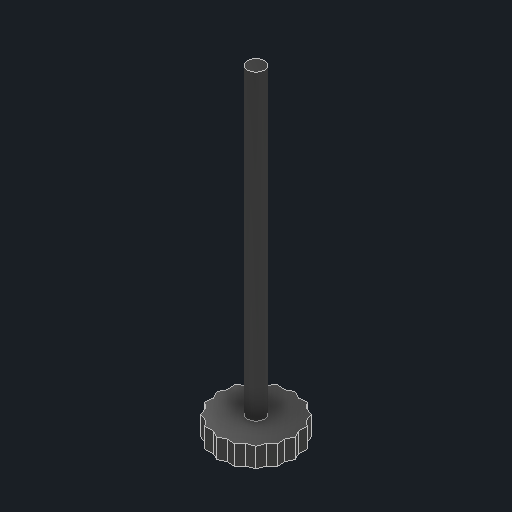
# Autodesk Inventor part: tripod_tension_rod
Saved by Autodesk Inventor 2027.1 (Build 311270010, 270A)
## iProperties
Created: 2026-11-04
Part Number: tripod_tension_rod
Material: Generic
Description: Centre tension rod + tray knob
Document SubType Name: Modeling
Designer: Claude (from photos)
Density: 1 g/cm^3
Appearance: Glossy - Black
Author: alexg
Autodesk Inventor part; units mm, degrees
ref_plane "YZ Plane" through (0, 0, 0) normal (1, 0, 0) x (0, 1, 0)
ref_plane "Work Plane1" through (0, -38, 0) normal (0, 1, 0) x (-1, 0, 0)
sketch "Centre rod M12 sketch" plane through (0, -38, 0) normal (0, 1, 0) x (-1, 0, 0)
  circle A0 centre (0, 0) radius 6
  constraints: 1 centre point
extrude "Centre rod M12" add sketch "Centre rod M12 sketch" against normal blind 236
ref_plane "Work Plane2" through (0, -254, 0) normal (0, 1, 0) x (-1, 0, 0)
sketch "Tension knob sketch" plane through (0, -254, 0) normal (0, 1, 0) x (-1, 0, 0)
  line L0 (-28, 0) -> (-25.5004, 5.0723)
  line L1 (-25.5004, 5.0723) -> (-25.8686, 10.7151)
  line L2 (-25.8686, 10.7151) -> (-21.6182, 14.4448)
  line L3 (-21.6182, 14.4448) -> (-19.799, 19.799)
  line L4 (-19.799, 19.799) -> (-14.4448, 21.6182)
  line L5 (-14.4448, 21.6182) -> (-10.7151, 25.8686)
  line L6 (-10.7151, 25.8686) -> (-5.0723, 25.5004)
  line L7 (-5.0723, 25.5004) -> (0, 28)
  line L8 (0, 28) -> (5.0723, 25.5004)
  line L9 (5.0723, 25.5004) -> (10.7151, 25.8686)
  line L10 (10.7151, 25.8686) -> (14.4448, 21.6182)
  line L11 (14.4448, 21.6182) -> (19.799, 19.799)
  line L12 (19.799, 19.799) -> (21.6182, 14.4448)
  line L13 (21.6182, 14.4448) -> (25.8686, 10.7151)
  line L14 (25.8686, 10.7151) -> (25.5004, 5.0723)
  line L15 (25.5004, 5.0723) -> (28, 0)
  line L16 (28, 0) -> (25.5004, -5.0723)
  line L17 (25.5004, -5.0723) -> (25.8686, -10.7151)
  line L18 (25.8686, -10.7151) -> (21.6182, -14.4448)
  line L19 (21.6182, -14.4448) -> (19.799, -19.799)
  line L20 (19.799, -19.799) -> (14.4448, -21.6182)
  line L21 (14.4448, -21.6182) -> (10.7151, -25.8686)
  line L22 (10.7151, -25.8686) -> (5.0723, -25.5004)
  line L23 (5.0723, -25.5004) -> (0, -28)
  line L24 (0, -28) -> (-5.0723, -25.5004)
  line L25 (-5.0723, -25.5004) -> (-10.7151, -25.8686)
  line L26 (-10.7151, -25.8686) -> (-14.4448, -21.6182)
  line L27 (-14.4448, -21.6182) -> (-19.799, -19.799)
  line L28 (-19.799, -19.799) -> (-21.6182, -14.4448)
  line L29 (-21.6182, -14.4448) -> (-25.8686, -10.7151)
  line L30 (-25.8686, -10.7151) -> (-25.5004, -5.0723)
  line L31 (-25.5004, -5.0723) -> (-28, 0)
  constraints: 64 end point
extrude "Tension knob" add sketch "Tension knob sketch" against normal blind 14
body "Solid1"
